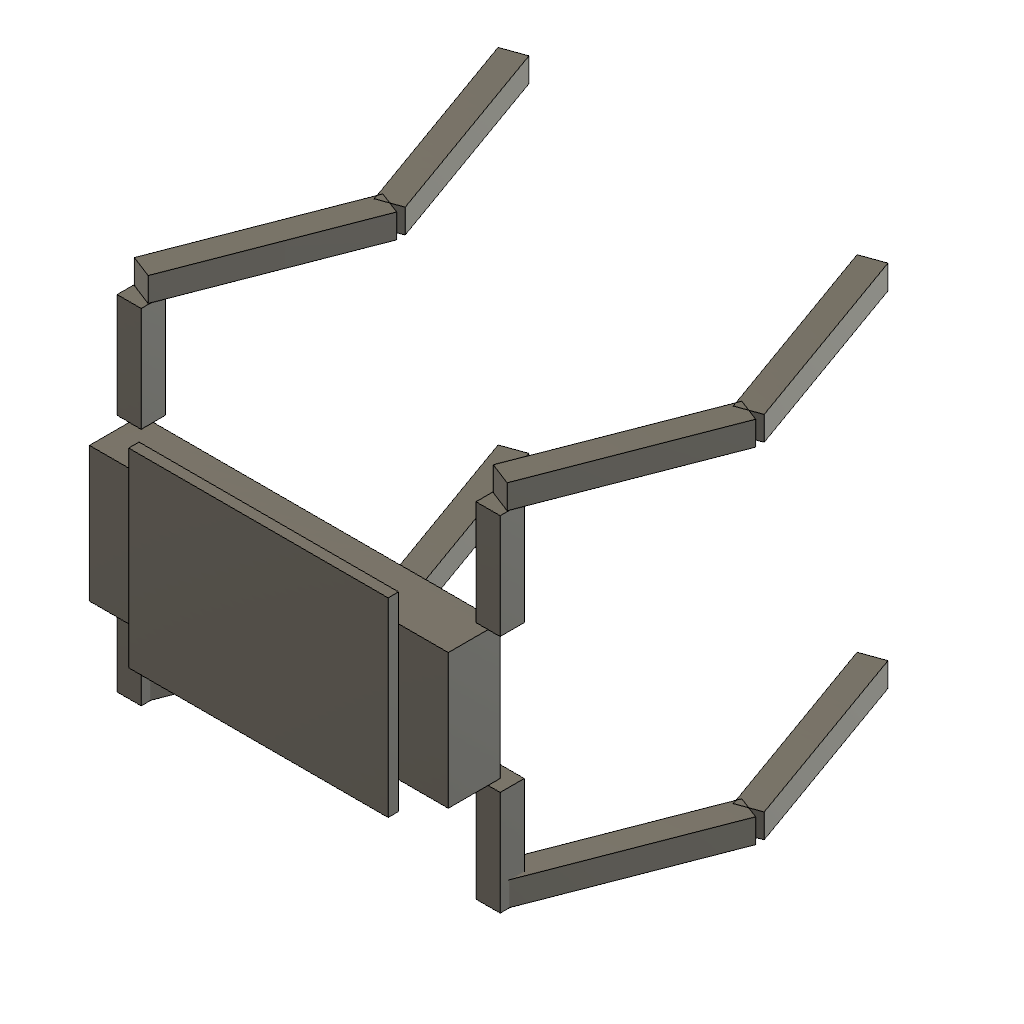
quadruped-layout-concept-not-printable (Autodesk Fusion 360 design; units mm, degrees)
part number: 2026-10-26-15-00-40-258
part number: 2026-10-26-15-00-40-357
part number: 2026-10-26-15-00-40-371
part number: 2026-10-26-15-00-40-381
part number: 2026-10-26-15-00-40-392
part number: 2026-10-26-15-00-40-406
part number: 2026-10-26-15-00-40-421
part number: 2026-10-26-15-00-40-434
part number: 2026-10-26-15-00-40-449
part number: 2026-10-26-15-00-40-466
part number: 2026-10-26-15-00-40-480
part number: 2026-10-26-15-00-40-499
part number: 2026-10-26-15-00-40-518
part number: 2026-10-26-15-00-40-534
part number: 2026-10-26-15-00-40-554
Autodesk Fusion 360 part; units mm, degrees
sketch "Sketch1" plane through (0, 0, 0) normal (0, 0, 1) x (1, 0, 0) in component "Body envelope - 207.5 x 78 x 30 mm"
  line L0 (-103.75, -39) -> (103.75, -39)
  line L1 (103.75, -39) -> (103.75, 39)
  line L2 (103.75, 39) -> (-103.75, 39)
  line L3 (-103.75, 39) -> (-103.75, -39)
extrude "Extrude1" add sketch "Sketch1" along normal blind 30 makes body 1 in component "Body envelope - 207.5 x 78 x 30 mm"
sketch "Sketch1 (2)" plane through (0, 0, 0) normal (0, 0, 1) x (1, 0, 0) in component "Arm mount envelope - fit unverified"
  line L0 (-75, -55) -> (75, -55)
  line L1 (75, -55) -> (75, 55)
  line L2 (75, 55) -> (-75, 55)
  line L3 (-75, 55) -> (-75, -55)
extrude "Extrude1'" add sketch "Sketch1 (2)" along normal blind 6 separate body makes body 2 in component "Arm mount envelope - fit unverified"
sketch "Sketch1 (3)" plane through (0, 0, 0) normal (0, 0, 1) x (1, 0, 0) in component "front left shoulder envelope"
  line L0 (96.75, 39) -> (110.75, 39)
  line L1 (110.75, 39) -> (110.75, 99.5)
  line L2 (110.75, 99.5) -> (96.75, 99.5)
  line L3 (96.75, 99.5) -> (96.75, 39)
extrude "Extrude1''" add sketch "Sketch1 (3)" along normal blind 14 separate body makes body 3 in component "front left shoulder envelope"
sketch "Sketch1 (4)" plane through (0, 0, 0) normal (0, 1, 0) x (1, 0, 0) in component "front left upper leg envelope"
  line L0 (110.2806, -217.7203) -> (150.2806, -114.0708)
  line L1 (150.2806, -114.0708) -> (137.2194, -109.0303)
  line L2 (137.2194, -109.0303) -> (97.2194, -212.6797)
  line L3 (97.2194, -212.6797) -> (110.2806, -217.7203)
extrude "Extrude1'''" add sketch "Sketch1 (4)" along normal blind 14 separate body makes body 4 in component "front left upper leg envelope"
sketch "Sketch1 (5)" plane through (0, 0, 0) normal (0, 1, 0) x (1, 0, 0) in component "front left lower leg envelope"
  line L0 (150.3391, -109.1877) -> (110.3391, 2.3572)
  line L1 (110.3391, 2.3572) -> (97.1609, -2.3686)
  line L2 (97.1609, -2.3686) -> (137.1609, -113.9134)
  line L3 (137.1609, -113.9134) -> (150.3391, -109.1877)
extrude "Extrude1''''" add sketch "Sketch1 (5)" along normal blind 14 separate body makes body 5 in component "front left lower leg envelope"
sketch "Sketch1 (6)" plane through (0, 0, 0) normal (0, 0, 1) x (1, 0, 0) in component "front right shoulder envelope"
  line L0 (96.75, -99.5) -> (110.75, -99.5)
  line L1 (110.75, -99.5) -> (110.75, -39)
  line L2 (110.75, -39) -> (96.75, -39)
  line L3 (96.75, -39) -> (96.75, -99.5)
extrude "Extrude1'''''" add sketch "Sketch1 (6)" along normal blind 14 separate body makes body 6 in component "front right shoulder envelope"
sketch "Sketch1 (7)" plane through (0, 0, 0) normal (0, 1, 0) x (1, 0, 0) in component "front right upper leg envelope"
  line L0 (110.2806, -217.7203) -> (150.2806, -114.0708)
  line L1 (150.2806, -114.0708) -> (137.2194, -109.0303)
  line L2 (137.2194, -109.0303) -> (97.2194, -212.6797)
  line L3 (97.2194, -212.6797) -> (110.2806, -217.7203)
extrude "Extrude1''''''" add sketch "Sketch1 (7)" along normal blind 14 separate body makes body 7 in component "front right upper leg envelope"
sketch "Sketch1 (8)" plane through (0, 0, 0) normal (0, 1, 0) x (1, 0, 0) in component "front right lower leg envelope"
  line L0 (150.3391, -109.1877) -> (110.3391, 2.3572)
  line L1 (110.3391, 2.3572) -> (97.1609, -2.3686)
  line L2 (97.1609, -2.3686) -> (137.1609, -113.9134)
  line L3 (137.1609, -113.9134) -> (150.3391, -109.1877)
extrude "Extrude1'''''''" add sketch "Sketch1 (8)" along normal blind 14 separate body makes body 8 in component "front right lower leg envelope"
sketch "Sketch1 (9)" plane through (0, 0, 0) normal (0, 0, 1) x (1, 0, 0) in component "rear left shoulder envelope"
  line L0 (-110.75, 39) -> (-96.75, 39)
  line L1 (-96.75, 39) -> (-96.75, 99.5)
  line L2 (-96.75, 99.5) -> (-110.75, 99.5)
  line L3 (-110.75, 99.5) -> (-110.75, 39)
extrude "Extrude1''''''''" add sketch "Sketch1 (9)" along normal blind 14 separate body makes body 9 in component "rear left shoulder envelope"
sketch "Sketch1 (10)" plane through (0, 0, 0) normal (0, 1, 0) x (1, 0, 0) in component "rear left upper leg envelope"
  line L0 (-97.2194, -217.7203) -> (-57.2194, -114.0708)
  line L1 (-57.2194, -114.0708) -> (-70.2806, -109.0303)
  line L2 (-70.2806, -109.0303) -> (-110.2806, -212.6797)
  line L3 (-110.2806, -212.6797) -> (-97.2194, -217.7203)
extrude "Extrude1'''''''''" add sketch "Sketch1 (10)" along normal blind 14 separate body makes body 10 in component "rear left upper leg envelope"
sketch "Sketch1 (11)" plane through (0, 0, 0) normal (0, 1, 0) x (1, 0, 0) in component "rear left lower leg envelope"
  line L0 (-57.1609, -109.1877) -> (-97.1609, 2.3572)
  line L1 (-97.1609, 2.3572) -> (-110.3391, -2.3686)
  line L2 (-110.3391, -2.3686) -> (-70.3391, -113.9134)
  line L3 (-70.3391, -113.9134) -> (-57.1609, -109.1877)
extrude "Extrude1''''''''''" add sketch "Sketch1 (11)" along normal blind 14 separate body makes body 11 in component "rear left lower leg envelope"
sketch "Sketch1 (12)" plane through (0, 0, 0) normal (0, 0, 1) x (1, 0, 0) in component "rear right shoulder envelope"
  line L0 (-110.75, -99.5) -> (-96.75, -99.5)
  line L1 (-96.75, -99.5) -> (-96.75, -39)
  line L2 (-96.75, -39) -> (-110.75, -39)
  line L3 (-110.75, -39) -> (-110.75, -99.5)
extrude "Extrude1'''''''''''" add sketch "Sketch1 (12)" along normal blind 14 separate body makes body 12 in component "rear right shoulder envelope"
sketch "Sketch1 (13)" plane through (0, 0, 0) normal (0, 1, 0) x (1, 0, 0) in component "rear right upper leg envelope"
  line L0 (-97.2194, -217.7203) -> (-57.2194, -114.0708)
  line L1 (-57.2194, -114.0708) -> (-70.2806, -109.0303)
  line L2 (-70.2806, -109.0303) -> (-110.2806, -212.6797)
  line L3 (-110.2806, -212.6797) -> (-97.2194, -217.7203)
extrude "Extrude1''''''''''''" add sketch "Sketch1 (13)" along normal blind 14 separate body makes body 13 in component "rear right upper leg envelope"
sketch "Sketch1 (14)" plane through (0, 0, 0) normal (0, 1, 0) x (1, 0, 0) in component "rear right lower leg envelope"
  line L0 (-57.1609, -109.1877) -> (-97.1609, 2.3572)
  line L1 (-97.1609, 2.3572) -> (-110.3391, -2.3686)
  line L2 (-110.3391, -2.3686) -> (-70.3391, -113.9134)
  line L3 (-70.3391, -113.9134) -> (-57.1609, -109.1877)
extrude "Extrude1'''''''''''''" add sketch "Sketch1 (14)" along normal blind 14 separate body makes body 14 in component "rear right lower leg envelope"
component "Body envelope - 207.5 x 78 x 30 mm" placed x (1, 0, 0) y (0, 1, 0) z (0, 0, 1) at (0, 0, 215.2)
component "Arm mount envelope - fit unverified" placed x (1, 0, 0) y (0, 1, 0) z (0, 0, 1) at (0, 0, 245.2)
component "front left shoulder envelope" placed x (1, 0, 0) y (0, 1, 0) z (0, 0, 1) at (0, 0, 208.2)
component "front left upper leg envelope" placed x (1, 0, 0) y (0, 1, 0) z (0, 0, 1) at (0, 99.5, 0)
component "front left lower leg envelope" placed x (1, 0, 0) y (0, 1, 0) z (0, 0, 1) at (0, 99.5, 0)
component "front right shoulder envelope" placed x (1, 0, 0) y (0, 1, 0) z (0, 0, 1) at (0, 0, 208.2)
component "front right upper leg envelope" placed x (1, 0, 0) y (0, 1, 0) z (0, 0, 1) at (0, -99.5, 0)
component "front right lower leg envelope" placed x (1, 0, 0) y (0, 1, 0) z (0, 0, 1) at (0, -99.5, 0)
component "rear left shoulder envelope" placed x (1, 0, 0) y (0, 1, 0) z (0, 0, 1) at (0, 0, 208.2)
component "rear left upper leg envelope" placed x (1, 0, 0) y (0, 1, 0) z (0, 0, 1) at (0, 99.5, 0)
component "rear left lower leg envelope" placed x (1, 0, 0) y (0, 1, 0) z (0, 0, 1) at (0, 99.5, 0)
component "rear right shoulder envelope" placed x (1, 0, 0) y (0, 1, 0) z (0, 0, 1) at (0, 0, 208.2)
component "rear right upper leg envelope" placed x (1, 0, 0) y (0, 1, 0) z (0, 0, 1) at (0, -99.5, 0)
component "rear right lower leg envelope" placed x (1, 0, 0) y (0, 1, 0) z (0, 0, 1) at (0, -99.5, 0)
